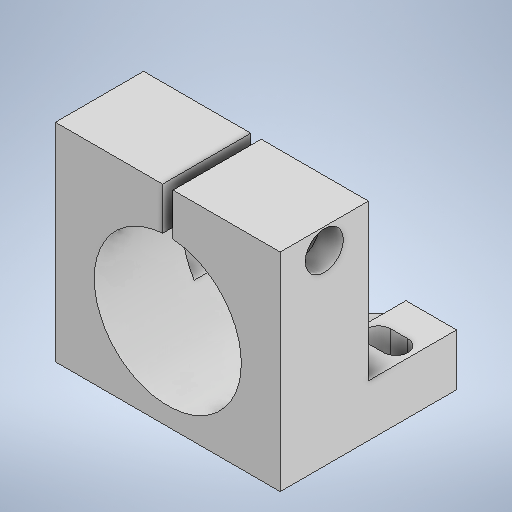
# Autodesk Inventor part: mancal motor traseiro
Saved by Autodesk Inventor 2025 (Build 290162000, 162)
## iProperties
Created: 2024-11-08
Part Number: mancal motor traseiro
Material: Genérico
Document SubType Name: Modeling
Designer: ALUNO
Density: 1 g/cm^3
Appearance: Padrão
Author: ALUNO
Autodesk Inventor part; units mm, degrees
ref_plane "YZ Plane" through (0, 0, 0) normal (1, 0, 0) x (0, 1, 0)
ref_plane "XZ Plane" through (0, 0, 0) normal (0, 1, 0) x (-1, 0, 0)
ref_plane "XY Plane" through (0, 0, 0) normal (0, 0, 1) x (1, 0, 0)
sketch "Esboço1" plane through (0, 0, 0) normal (1, 0, 0) x (0, 1, 0)
  line L0 (58.4741, 86.0625) -> (58.4741, 73.5323)
  line L1 (58.4741, 73.5323) -> (13.4741, 73.5323)
  line L2 (13.4741, 73.5323) -> (13.4741, 48.0323)
  line L3 (13.4741, 48.0323) -> (-1.5259, 48.0323)
  line L4 (-1.5259, 48.0323) -> (-1.5259, 99.0323)
  line L5 (-1.5259, 99.0323) -> (58.4741, 99.0323)
  line L6 (58.4741, 99.0323) -> (58.4741, 86.0625)
  point P0 (0, 0)
  dimension "d0" = 25.5
  dimension "d1" = 25.5
  dimension "d2" = 60
  dimension "d3" = 15
  constraints: 14 end point, 5 perpendicular, 1 collinear, 1 point on line, 1 vertical
  measures "d0" distance of L0.end L5.end
  measures "d1" distance of L1.end L2.end
  measures "d2" distance of L4.end L5.end
  measures "d3" distance of L2.end L3.end
extrude "Extrusão1" add sketch "Esboço1" against normal blind 65
sketch "Esboço3" plane through (0, -1.5259, 99.0323) normal (0, 0, 1) x (1, 0, 0)
  line L0 (0, 0) -> (-65, 0) projected
  line L1 (-32.5, 0) -> (-32.5, 26.5)
  circle A0 centre (-32.5, 26.5) radius 21.25
  point P0 (0, 1.5259)
  dimension "d6" = 26.5
  dimension "d7" = 42.5
  constraints: 2 end point, 1 centre point, 1 coincident, 1 midpoint, 1 vertical
  measures "d6" distance of L1.start L1.end
  measures "d7" diameter of A0
extrude "Extrusão2" cut sketch "Esboço3" against normal blind 55
sketch "Esboço4" plane through (0, -1.5259, 99.0323) normal (0, 0, 1) x (1, 0, 0)
  circle A0 centre (-32.5, 26.5) radius 21.25 projected
  line L0 (0, 60) -> (-65, 60) projected
  line L1 (-34, 30.0239) -> (-34, 65.4761)
  line L2 (-34, 65.4761) -> (-31, 65.4761)
  line L3 (-31, 65.4761) -> (-31, 30.0239)
  line L4 (-31, 30.0239) -> (-34, 30.0239)
  line L5 (-34, 30.0239) -> (-31, 65.4761) construction
  line L6 (-34, 65.4761) -> (-31, 30.0239) construction
  point P0 (0, 1.5259)
  point P1 (-32.5, 47.75)
  dimension "d10" = 3
  constraints: 12 end point, 2 midpoint, 2 parallel, 1 perpendicular, 1 vertical, 1 vertical alignment, 1 other
  measures "d10" distance of L1.end L2.end
extrude "Extrusão3" cut sketch "Esboço4" against normal blind 65 contours L3 L4 L1 A0 | A0 L1 L0 L3 | L0 L1 L2 L3 picked at (-32.6668, 35.9306)
sketch "Esboço5" plane through (0, 0, 0) normal (1, 0, 0) x (0, 0, -1)
  line L0 (-73.5323, 58.4741) -> (-99.0323, 58.4741) projected
  line L1 (-73.5323, 13.4741) -> (-73.5323, 58.4741) projected
  point P0 (0, 0)
  point P1 (-86.2823, 52.4741)
  dimension "d13" = 6
  dimension "d14" = 12.75
  measures "d13" distance from line of L0 point (-86.282, 52.474)
  measures "d14" distance from line of L1 point (-86.282, 52.474)
hole "Furo1" at (0, 52.4741, 86.2823) direction (-1, 0, 0) diameter 7 depth 32.5 counterbore diameter 11 counterbore depth 7
sketch "Esboço6" plane through (-34, 46.1711, 99.0323) normal (1, 0, 0) x (0, 0, -1)
  circle A0 centre (12.75, 6.303) radius 3.5 projected
  point P0 (99.0323, -46.1711)
  constraints: 1 coincident
hole "Furo2" at (-34, 52.4741, 86.2823) direction (-1, 0, 0) diameter 4.917 end through all thread size "M6x1" class "6H" standard "ISO Metric profile"
sketch "Esboço7" plane through (0, 13.4741, 73.5323) normal (0, 1, 0) x (1, 0, 0)
  line L0 (0, 25.5) -> (0, 0) projected
  line L1 (0, 25.5) -> (-14.6307, 25.5) projected
  line L2 (-9.8153, 9.25) -> (-4.8153, 9.25)
  line L3 (-1.3153, 12.75) -> (-1.3153, 12.75)
  line L4 (-4.8153, 16.25) -> (-9.8153, 16.25)
  line L5 (-13.3153, 12.75) -> (-13.3153, 12.75)
  line L6 (-13.3153, 9.25) -> (-1.3153, 16.25) construction
  line L7 (-1.3153, 9.25) -> (-13.3153, 16.25) construction
  arc A0 (-9.8153, 16.25) -> (-13.3153, 12.75) centre (-9.8153, 12.75) ccw
  arc A1 (-13.3153, 12.75) -> (-9.8153, 9.25) centre (-9.8153, 12.75) ccw
  arc A2 (-4.8153, 9.25) -> (-1.3153, 12.75) centre (-4.8153, 12.75) ccw
  arc A3 (-1.3153, 12.75) -> (-4.8153, 16.25) centre (-4.8153, 12.75) ccw
  line L8 (-50.3693, 0) -> (-50.3693, 25.5) projected
  line L9 (-60.1989, 9.25) -> (-55.1989, 9.25)
  line L10 (-51.6989, 12.75) -> (-51.6989, 12.75)
  line L11 (-55.1989, 16.25) -> (-60.1989, 16.25)
  line L12 (-63.6989, 12.75) -> (-63.6989, 12.75)
  line L13 (-63.6989, 9.25) -> (-51.6989, 16.25) construction
  line L14 (-51.6989, 9.25) -> (-63.6989, 16.25) construction
  arc A4 (-60.1989, 16.25) -> (-63.6989, 12.75) centre (-60.1989, 12.75) ccw
  arc A5 (-63.6989, 12.75) -> (-60.1989, 9.25) centre (-60.1989, 12.75) ccw
  arc A6 (-55.1989, 9.25) -> (-51.6989, 12.75) centre (-55.1989, 12.75) ccw
  arc A7 (-51.6989, 12.75) -> (-55.1989, 16.25) centre (-55.1989, 12.75) ccw
  point P0 (0, 73.5323)
  point P1 (-7.3153, 12.75)
  point P2 (-57.6989, 12.75)
  point P3 (-51.6989, 12.75)
  point P4 (-63.6989, 12.75)
  point P5 (-1.3153, 12.75)
  point P6 (-13.3153, 12.75)
  dimension "d29" = 7
  dimension "d30" = 12
  dimension "d31" = 3.5
  dimension "d32" = 3.5
  dimension "d33" = 12
  dimension "d34" = 3.5
  constraints: 24 end point, 16 point on circle, 16 point on line, 16 tangent, 8 centre point, 5 equal radius, 4 midpoint, 4 parallel, 2 horizontal, 2 perpendicular
  measures "d29" distance of L7.start L6.end
  measures "d30" distance of L6.end L7.end
  measures "d31" radius of A0
  measures "d32" radius of A1
  measures "d33" distance of L13.end L14.end
  measures "d34" radius of A4
extrude "Extrusão4" cut sketch "Esboço7" against normal blind 65
